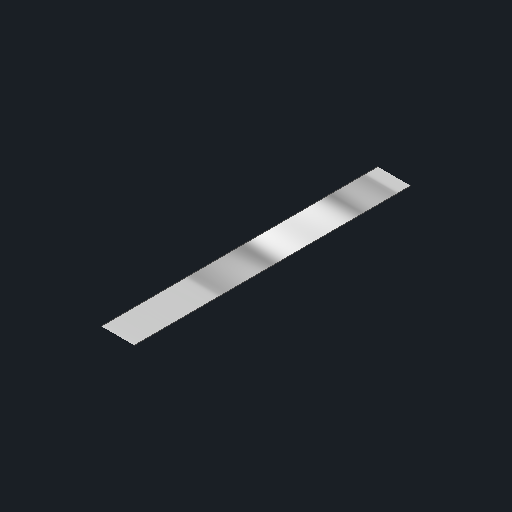
# Autodesk Inventor part: c8n_secondary_mirror
Saved by Autodesk Inventor 2027.1 (Build 311270010, 270A)
## iProperties
Created: 2026-11-04
Part Number: c8n_secondary_mirror
Material: Generic
Description: Secondary flat, 50 mm minor axis, 6 thick
Document SubType Name: Modeling
Designer: Claude (from photos)
Density: 1 g/cm^3
Appearance: Mirror
Author: alexg
Autodesk Inventor part; units mm, degrees
ref_plane "XZ Plane" through (0, 0, 0) normal (0, 1, 0) x (-1, 0, 0)
ref_plane "XY Plane" through (0, 0, 0) normal (0, 0, 1) x (1, 0, 0)
ref_plane "Work Plane1" through (802, 0, 0) normal (1, 0, 0) x (0, 1, 0)
sketch "Blank sketch" plane through (802, 0, 0) normal (1, 0, 0) x (0, 1, 0)
  circle A0 centre (0, 0) radius 25
  constraints: 1 centre point
extrude "Blank" add sketch "Blank sketch" along normal blind 90
sketch "Front face 45 sketch" plane through (0, 0, 0) normal (0, 0, 1) x (1, 0, 0)
  line L0 (762, -30) -> (812, -30)
  line L1 (812, -30) -> (872, 30)
  line L2 (872, 30) -> (762, 30)
  line L3 (762, 30) -> (762, -30)
  constraints: 8 end point
extrude "Front face 45" cut sketch "Front face 45 sketch" along normal mid plane 80
sketch "Back face 45 sketch" plane through (0, 0, 0) normal (0, 0, 1) x (1, 0, 0)
  line L0 (820.4853, -30) -> (942, -30)
  line L1 (942, -30) -> (942, 30)
  line L2 (942, 30) -> (880.4853, 30)
  line L3 (880.4853, 30) -> (820.4853, -30)
  constraints: 8 end point
extrude "Back face 45" cut sketch "Back face 45 sketch" along normal mid plane 80
body "Solid1"
